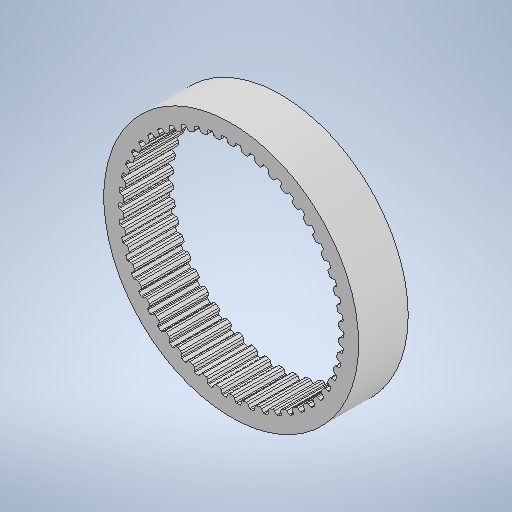
# Autodesk Inventor part: 3D_belt-MXL-50
Saved by Autodesk Inventor 2025.3 (Build 293356030, 356C)
## iProperties
Created: 2026-02-24
Part Number: 3D_belt-MXL-50
Material: 一般
Document SubType Name: Modeling
Designer: ibuki_ono
Density: 1 g/cm^3
Appearance: 既定
Author: ibuki_ono
## iProperties of the stored document 3D_belt-MXL-50_3D プリント.ipt
Created: 2026-02-24
Part Number: 3D_belt-MXL-50_3D プリント
Material: 一般
Document SubType Name: Modeling
Designer: ibuki_ono
Density: 1 g/cm^3
Appearance: 既定
Author: ibuki_ono
Autodesk Inventor part; units mm, degrees
ref_plane "YZ Plane" through (0, 0, 0) normal (1, 0, 0) x (0, 1, 0)
ref_plane "XZ Plane" through (0, 0, 0) normal (0, 1, 0) x (-1, 0, 0)
ref_plane "XY Plane" through (0, 0, 0) normal (0, 0, 1) x (1, 0, 0)
sketch "スケッチ1" plane through (0, 0, 0) normal (0, 0, 1) x (1, 0, 0)
  arc A0 (2.7438, 15.6779) -> (2.6089, 15.6108) centre (2.7219, 15.5528) ccw
  line L0 (2.6089, 15.6108) -> (2.406, 15.2159)
  arc A1 (2.1482, 15.08) -> (2.406, 15.2159) centre (2.18, 15.332) ccw
  line L1 (2.1482, 15.08) -> (1.6695, 15.1405)
  arc A2 (1.4537, 15.3362) -> (1.6695, 15.1405) centre (1.7014, 15.3925) ccw
  line L2 (1.4537, 15.3362) -> (1.3553, 15.7692)
  arc A3 (1.3553, 15.7692) -> (1.2414, 15.8677) centre (1.2315, 15.741) ccw
  arc A4 (1.2414, 15.8677) -> (0.7572, 15.8981) centre (0, 0) ccw
  arc A5 (0.7572, 15.8981) -> (0.6318, 15.8147) centre (0.7511, 15.7713) ccw
  line L3 (0.6318, 15.8147) -> (0.4799, 15.3975)
  arc A6 (0.2412, 15.2303) -> (0.4799, 15.3975) centre (0.2412, 15.4843) ccw
  line L4 (0.2412, 15.2303) -> (-0.2412, 15.2303)
  arc A7 (-0.4799, 15.3975) -> (-0.2412, 15.2303) centre (-0.2412, 15.4843) ccw
  line L5 (-0.4799, 15.3975) -> (-0.6318, 15.8147)
  arc A8 (-0.6318, 15.8147) -> (-0.7572, 15.8981) centre (-0.7511, 15.7713) ccw
  arc A9 (-0.7572, 15.8981) -> (-1.2414, 15.8677) centre (0, 0) ccw
  arc A10 (-1.2414, 15.8677) -> (-1.3553, 15.7692) centre (-1.2315, 15.741) ccw
  line L6 (-1.3553, 15.7692) -> (-1.4537, 15.3362)
  arc A11 (-1.6695, 15.1405) -> (-1.4537, 15.3362) centre (-1.7014, 15.3925) ccw
  line L7 (-1.6695, 15.1405) -> (-2.1482, 15.08)
  arc A12 (-2.406, 15.2159) -> (-2.1482, 15.08) centre (-2.18, 15.332) ccw
  line L8 (-2.406, 15.2159) -> (-2.6089, 15.6108)
  arc A13 (-2.6089, 15.6108) -> (-2.7438, 15.6779) centre (-2.7219, 15.5528) ccw
  arc A14 (-2.7438, 15.6779) -> (-3.2203, 15.587) centre (0, 0) ccw
  arc A15 (-3.2203, 15.587) -> (-3.321, 15.475) centre (-3.1946, 15.4626) ccw
  line L9 (-3.321, 15.475) -> (-3.3643, 15.0331)
  arc A16 (-3.554, 14.8118) -> (-3.3643, 15.0331) centre (-3.6171, 15.0579) ccw
  line L10 (-3.554, 14.8118) -> (-4.0213, 14.6919)
  arc A17 (-4.294, 14.7944) -> (-4.0213, 14.6919) centre (-4.0845, 14.9379) ccw
  line L11 (-4.294, 14.7944) -> (-4.5449, 15.1607)
  arc A18 (-4.5449, 15.1607) -> (-4.6871, 15.2104) centre (-4.6497, 15.089) ccw
  arc A19 (-4.6871, 15.2104) -> (-5.1485, 15.0604) centre (0, 0) ccw
  arc A20 (-5.1485, 15.0604) -> (-5.2344, 14.9367) centre (-5.1074, 14.9403) ccw
  line L12 (-5.2344, 14.9367) -> (-5.222, 14.4929)
  arc A21 (-5.3824, 14.2496) -> (-5.222, 14.4929) centre (-5.4759, 14.4858) ccw
  line L13 (-5.3824, 14.2496) -> (-5.831, 14.072)
  arc A22 (-6.1144, 14.1395) -> (-5.831, 14.072) centre (-5.9245, 14.3082) ccw
  line L14 (-6.1144, 14.1395) -> (-6.4092, 14.4716)
  arc A23 (-6.4092, 14.4716) -> (-6.5565, 14.503) centre (-6.5042, 14.3872) ccw
  arc A24 (-6.5565, 14.503) -> (-6.9955, 14.2964) centre (0, 0) ccw
  arc A25 (-6.9955, 14.2964) -> (-7.0651, 14.1629) centre (-6.9396, 14.1823) ccw
  line L15 (-7.0651, 14.1629) -> (-6.9972, 13.7241)
  arc A26 (-7.1259, 13.4627) -> (-6.9972, 13.7241) centre (-7.2482, 13.6853) ccw
  line L16 (-7.1259, 13.4627) -> (-7.5487, 13.2302)
  arc A27 (-7.8384, 13.2617) -> (-7.5487, 13.2302) centre (-7.671, 13.4528) ccw
  line L17 (-7.8384, 13.2617) -> (-8.1724, 13.5542)
  arc A28 (-8.1724, 13.5542) -> (-8.3225, 13.5669) centre (-8.2561, 13.4586) ccw
  arc A29 (-8.3225, 13.5669) -> (-8.7321, 13.3069) centre (0, 0) ccw
  arc A30 (-8.7321, 13.3069) -> (-8.7845, 13.1657) centre (-8.6624, 13.2007) ccw
  line L18 (-8.7845, 13.1657) -> (-8.6621, 12.7389)
  arc A31 (-8.757, 12.4634) -> (-8.6621, 12.7389) centre (-8.9063, 12.6689) ccw
  line L19 (-8.757, 12.4634) -> (-9.1473, 12.1798)
  arc A32 (-9.4387, 12.1747) -> (-9.1473, 12.1798) centre (-9.2966, 12.3853) ccw
  line L20 (-9.4387, 12.1747) -> (-9.8068, 12.423)
  arc A33 (-9.8068, 12.423) -> (-9.9572, 12.4168) centre (-9.8778, 12.3177) ccw
  arc A34 (-9.9572, 12.4168) -> (-10.3311, 12.1076) centre (0, 0) ccw
  arc A35 (-10.3311, 12.1076) -> (-10.3654, 11.9609) centre (-10.2486, 12.0109) ccw
  line L21 (-10.3654, 11.9609) -> (-10.1904, 11.5528)
  arc A36 (-10.25, 11.2676) -> (-10.1904, 11.5528) centre (-10.4239, 11.4527) ccw
  line L22 (-10.25, 11.2676) -> (-10.6017, 10.9373)
  arc A37 (-10.8901, 10.8957) -> (-10.6017, 10.9373) centre (-10.7756, 11.1225) ccw
  line L23 (-10.8901, 10.8957) -> (-11.2865, 11.0959)
  arc A38 (-11.2865, 11.0959) -> (-11.435, 11.0709) centre (-11.3437, 10.9826) ccw
  arc A39 (-11.435, 11.0709) -> (-11.7671, 10.7173) centre (0, 0) ccw
  arc A40 (-11.7671, 10.7173) -> (-11.7827, 10.5675) centre (-11.6732, 10.6317) ccw
  line L24 (-11.7827, 10.5675) -> (-11.558, 10.1845)
  arc A41 (-11.5814, 9.8941) -> (-11.558, 10.1845) centre (-11.7771, 10.056) ccw
  line L25 (-11.5814, 9.8941) -> (-11.889, 9.5223)
  arc A42 (-12.1699, 9.4449) -> (-11.889, 9.5223) centre (-12.0847, 9.6842) ccw
  line L26 (-12.1699, 9.4449) -> (-12.5882, 9.5939)
  arc A43 (-12.5882, 9.5939) -> (-12.7324, 9.5504) centre (-12.6308, 9.4742) ccw
  arc A44 (-12.7324, 9.5504) -> (-13.0175, 9.1579) centre (0, 0) ccw
  arc A45 (-13.0175, 9.1579) -> (-13.0143, 9.0074) centre (-12.9136, 9.0849) ccw
  line L27 (-13.0143, 9.0074) -> (-12.7434, 8.6556)
  arc A46 (-12.7301, 8.3645) -> (-12.7434, 8.6556) centre (-12.9446, 8.5006) ccw
  line L28 (-12.7301, 8.3645) -> (-12.9887, 7.9571)
  arc A47 (-13.2577, 7.8452) -> (-12.9887, 7.9571) centre (-13.2031, 8.0932) ccw
  line L29 (-13.2577, 7.8452) -> (-13.6913, 7.9405)
  arc A48 (-13.6913, 7.9405) -> (-13.8289, 7.8793) centre (-13.7186, 7.8165) ccw
  arc A49 (-13.8289, 7.8793) -> (-14.0627, 7.4542) centre (0, 0) ccw
  arc A50 (-14.0627, 7.4542) -> (-14.0406, 7.3052) centre (-13.9505, 7.3947) ccw
  line L30 (-14.0406, 7.3052) -> (-13.7277, 6.9902)
  arc A51 (-13.6781, 6.7031) -> (-13.7277, 6.9902) centre (-13.9079, 6.8112) ccw
  line L31 (-13.6781, 6.7031) -> (-13.8835, 6.2665)
  arc A52 (-14.1364, 6.1217) -> (-13.8835, 6.2665) centre (-14.1134, 6.3746) ccw
  line L32 (-14.1364, 6.1217) -> (-14.5786, 6.1619)
  arc A53 (-14.5786, 6.1619) -> (-14.7074, 6.084) centre (-14.5901, 6.0354) ccw
  arc A54 (-14.7074, 6.084) -> (-14.886, 5.6329) centre (0, 0) ccw
  arc A55 (-14.886, 5.6329) -> (-14.8454, 5.4879) centre (-14.7673, 5.588) ccw
  line L33 (-14.8454, 5.4879) -> (-14.4956, 5.2145)
  arc A56 (-14.4104, 4.9359) -> (-14.4956, 5.2145) centre (-14.6519, 5.0144) ccw
  line L34 (-14.4104, 4.9359) -> (-14.5595, 4.477)
  arc A57 (-14.7922, 4.3016) -> (-14.5595, 4.477) centre (-14.801, 4.5555) ccw
  line L35 (-14.7922, 4.3016) -> (-15.2359, 4.2861)
  arc A58 (-15.2359, 4.2861) -> (-15.354, 4.1927) centre (-15.2315, 4.1592) ccw
  arc A59 (-15.354, 4.1927) -> (-15.4746, 3.7228) centre (0, 0) ccw
  arc A60 (-15.4746, 3.7228) -> (-15.4162, 3.584) centre (-15.3512, 3.6931) ccw
  line L36 (-15.4162, 3.584) -> (-15.0348, 3.3566)
  arc A61 (-14.9154, 3.0909) -> (-15.0348, 3.3566) centre (-15.1649, 3.1385) ccw
  line L37 (-14.9154, 3.0909) -> (-15.0058, 2.6169)
  arc A62 (-15.2147, 2.4138) -> (-15.0058, 2.6169) centre (-15.2553, 2.6645) ccw
  line L38 (-15.2147, 2.4138) -> (-15.653, 2.3428)
  arc A63 (-15.653, 2.3428) -> (-15.7584, 2.2353) centre (-15.6327, 2.2174) ccw
  arc A64 (-15.7584, 2.2353) -> (-15.8192, 1.7539) centre (0, 0) ccw
  arc A65 (-15.8192, 1.7539) -> (-15.7438, 1.6236) centre (-15.693, 1.7399) ccw
  line L39 (-15.7438, 1.6236) -> (-15.337, 1.4458)
  arc A66 (-15.1851, 1.1971) -> (-15.337, 1.4458) centre (-15.4386, 1.213) ccw
  line L40 (-15.1851, 1.1971) -> (-15.2154, 0.7155)
  arc A67 (-15.3972, 0.4878) -> (-15.2154, 0.7155) centre (-15.4689, 0.7315) ccw
  line L41 (-15.3972, 0.4878) -> (-15.8232, 0.3625)
  arc A68 (-15.8232, 0.3625) -> (-15.9143, 0.2426) centre (-15.7873, 0.2406) ccw
  arc A69 (-15.9143, 0.2426) -> (-15.9143, -0.2426) centre (0, 0) ccw
  arc A70 (-15.9143, -0.2426) -> (-15.8232, -0.3625) centre (-15.7873, -0.2406) ccw
  line L42 (-15.8232, -0.3625) -> (-15.3972, -0.4878)
  arc A71 (-15.2154, -0.7155) -> (-15.3972, -0.4878) centre (-15.4689, -0.7315) ccw
  line L43 (-15.2154, -0.7155) -> (-15.1851, -1.1971)
  arc A72 (-15.337, -1.4458) -> (-15.1851, -1.1971) centre (-15.4386, -1.213) ccw
  line L44 (-15.337, -1.4458) -> (-15.7438, -1.6236)
  arc A73 (-15.7438, -1.6236) -> (-15.8192, -1.7539) centre (-15.693, -1.7399) ccw
  arc A74 (-15.8192, -1.7539) -> (-15.7584, -2.2353) centre (0, 0) ccw
  arc A75 (-15.7584, -2.2353) -> (-15.653, -2.3428) centre (-15.6327, -2.2174) ccw
  line L45 (-15.653, -2.3428) -> (-15.2147, -2.4138)
  arc A76 (-15.0058, -2.6169) -> (-15.2147, -2.4138) centre (-15.2553, -2.6645) ccw
  line L46 (-15.0058, -2.6169) -> (-14.9154, -3.0909)
  arc A77 (-15.0348, -3.3566) -> (-14.9154, -3.0909) centre (-15.1649, -3.1385) ccw
  line L47 (-15.0348, -3.3566) -> (-15.4162, -3.584)
  arc A78 (-15.4162, -3.584) -> (-15.4746, -3.7228) centre (-15.3512, -3.6931) ccw
  arc A79 (-15.4746, -3.7228) -> (-15.354, -4.1927) centre (0, 0) ccw
  arc A80 (-15.354, -4.1927) -> (-15.2359, -4.2861) centre (-15.2315, -4.1592) ccw
  line L48 (-15.2359, -4.2861) -> (-14.7922, -4.3016)
  arc A81 (-14.5595, -4.477) -> (-14.7922, -4.3016) centre (-14.801, -4.5555) ccw
  line L49 (-14.5595, -4.477) -> (-14.4104, -4.9359)
  arc A82 (-14.4956, -5.2145) -> (-14.4104, -4.9359) centre (-14.6519, -5.0144) ccw
  line L50 (-14.4956, -5.2145) -> (-14.8454, -5.4879)
  arc A83 (-14.8454, -5.4879) -> (-14.886, -5.6329) centre (-14.7673, -5.588) ccw
  arc A84 (-14.886, -5.6329) -> (-14.7074, -6.084) centre (0, 0) ccw
  arc A85 (-14.7074, -6.084) -> (-14.5786, -6.1619) centre (-14.5901, -6.0354) ccw
  line L51 (-14.5786, -6.1619) -> (-14.1364, -6.1217)
  arc A86 (-13.8835, -6.2665) -> (-14.1364, -6.1217) centre (-14.1134, -6.3746) ccw
  line L52 (-13.8835, -6.2665) -> (-13.6781, -6.7031)
  arc A87 (-13.7277, -6.9902) -> (-13.6781, -6.7031) centre (-13.9079, -6.8112) ccw
  line L53 (-13.7277, -6.9902) -> (-14.0406, -7.3052)
  arc A88 (-14.0406, -7.3052) -> (-14.0627, -7.4542) centre (-13.9505, -7.3947) ccw
  arc A89 (-14.0627, -7.4542) -> (-13.8289, -7.8793) centre (0, 0) ccw
  arc A90 (-13.8289, -7.8793) -> (-13.6913, -7.9405) centre (-13.7186, -7.8165) ccw
  line L54 (-13.6913, -7.9405) -> (-13.2577, -7.8452)
  arc A91 (-12.9887, -7.9571) -> (-13.2577, -7.8452) centre (-13.2031, -8.0932) ccw
  line L55 (-12.9887, -7.9571) -> (-12.7301, -8.3645)
  arc A92 (-12.7434, -8.6556) -> (-12.7301, -8.3645) centre (-12.9446, -8.5006) ccw
  line L56 (-12.7434, -8.6556) -> (-13.0143, -9.0074)
  arc A93 (-13.0143, -9.0074) -> (-13.0175, -9.1579) centre (-12.9136, -9.0849) ccw
  arc A94 (-13.0175, -9.1579) -> (-12.7324, -9.5504) centre (0, 0) ccw
  arc A95 (-12.7324, -9.5504) -> (-12.5882, -9.5939) centre (-12.6308, -9.4742) ccw
  line L57 (-12.5882, -9.5939) -> (-12.1699, -9.4449)
  arc A96 (-11.889, -9.5223) -> (-12.1699, -9.4449) centre (-12.0847, -9.6842) ccw
  line L58 (-11.889, -9.5223) -> (-11.5814, -9.8941)
  arc A97 (-11.558, -10.1845) -> (-11.5814, -9.8941) centre (-11.7771, -10.056) ccw
  line L59 (-11.558, -10.1845) -> (-11.7827, -10.5675)
  arc A98 (-11.7827, -10.5675) -> (-11.7671, -10.7173) centre (-11.6732, -10.6317) ccw
  arc A99 (-11.7671, -10.7173) -> (-11.435, -11.0709) centre (0, 0) ccw
  arc A100 (-11.435, -11.0709) -> (-11.2865, -11.0959) centre (-11.3437, -10.9826) ccw
  line L60 (-11.2865, -11.0959) -> (-10.8901, -10.8957)
  arc A101 (-10.6017, -10.9373) -> (-10.8901, -10.8957) centre (-10.7756, -11.1225) ccw
  line L61 (-10.6017, -10.9373) -> (-10.25, -11.2676)
  arc A102 (-10.1904, -11.5528) -> (-10.25, -11.2676) centre (-10.4239, -11.4527) ccw
  line L62 (-10.1904, -11.5528) -> (-10.3654, -11.9609)
  arc A103 (-10.3654, -11.9609) -> (-10.3311, -12.1076) centre (-10.2486, -12.0109) ccw
  arc A104 (-10.3311, -12.1076) -> (-9.9572, -12.4168) centre (0, 0) ccw
  arc A105 (-9.9572, -12.4168) -> (-9.8068, -12.423) centre (-9.8778, -12.3177) ccw
  line L63 (-9.8068, -12.423) -> (-9.4387, -12.1747)
  arc A106 (-9.1473, -12.1798) -> (-9.4387, -12.1747) centre (-9.2966, -12.3853) ccw
  line L64 (-9.1473, -12.1798) -> (-8.757, -12.4634)
  arc A107 (-8.6621, -12.7389) -> (-8.757, -12.4634) centre (-8.9063, -12.6689) ccw
  line L65 (-8.6621, -12.7389) -> (-8.7845, -13.1657)
  arc A108 (-8.7845, -13.1657) -> (-8.7321, -13.3069) centre (-8.6624, -13.2007) ccw
  arc A109 (-8.7321, -13.3069) -> (-8.3225, -13.5669) centre (0, 0) ccw
  arc A110 (-8.3225, -13.5669) -> (-8.1724, -13.5542) centre (-8.2561, -13.4586) ccw
  line L66 (-8.1724, -13.5542) -> (-7.8384, -13.2617)
  arc A111 (-7.5487, -13.2302) -> (-7.8384, -13.2617) centre (-7.671, -13.4528) ccw
  line L67 (-7.5487, -13.2302) -> (-7.1259, -13.4627)
  arc A112 (-6.9972, -13.7241) -> (-7.1259, -13.4627) centre (-7.2482, -13.6853) ccw
  line L68 (-6.9972, -13.7241) -> (-7.0651, -14.1629)
  arc A113 (-7.0651, -14.1629) -> (-6.9955, -14.2964) centre (-6.9396, -14.1823) ccw
  arc A114 (-6.9955, -14.2964) -> (-6.5565, -14.503) centre (0, 0) ccw
  arc A115 (-6.5565, -14.503) -> (-6.4092, -14.4716) centre (-6.5042, -14.3872) ccw
  line L69 (-6.4092, -14.4716) -> (-6.1144, -14.1395)
  arc A116 (-5.831, -14.072) -> (-6.1144, -14.1395) centre (-5.9245, -14.3082) ccw
  line L70 (-5.831, -14.072) -> (-5.3824, -14.2496)
  arc A117 (-5.222, -14.4929) -> (-5.3824, -14.2496) centre (-5.4759, -14.4858) ccw
  line L71 (-5.222, -14.4929) -> (-5.2344, -14.9367)
  arc A118 (-5.2344, -14.9367) -> (-5.1485, -15.0604) centre (-5.1074, -14.9403) ccw
  arc A119 (-5.1485, -15.0604) -> (-4.6871, -15.2104) centre (0, 0) ccw
  arc A120 (-4.6871, -15.2104) -> (-4.5449, -15.1607) centre (-4.6497, -15.089) ccw
  line L72 (-4.5449, -15.1607) -> (-4.294, -14.7944)
  arc A121 (-4.0213, -14.6919) -> (-4.294, -14.7944) centre (-4.0845, -14.9379) ccw
  line L73 (-4.0213, -14.6919) -> (-3.554, -14.8118)
  arc A122 (-3.3643, -15.0331) -> (-3.554, -14.8118) centre (-3.6171, -15.0579) ccw
  line L74 (-3.3643, -15.0331) -> (-3.321, -15.475)
  arc A123 (-3.321, -15.475) -> (-3.2203, -15.587) centre (-3.1946, -15.4626) ccw
  arc A124 (-3.2203, -15.587) -> (-2.7438, -15.6779) centre (0, 0) ccw
  arc A125 (-2.7438, -15.6779) -> (-2.6089, -15.6108) centre (-2.7219, -15.5528) ccw
  line L75 (-2.6089, -15.6108) -> (-2.406, -15.2159)
  arc A126 (-2.1482, -15.08) -> (-2.406, -15.2159) centre (-2.18, -15.332) ccw
  line L76 (-2.1482, -15.08) -> (-1.6695, -15.1405)
  arc A127 (-1.4537, -15.3362) -> (-1.6695, -15.1405) centre (-1.7014, -15.3925) ccw
  line L77 (-1.4537, -15.3362) -> (-1.3553, -15.7692)
  arc A128 (-1.3553, -15.7692) -> (-1.2414, -15.8677) centre (-1.2315, -15.741) ccw
  arc A129 (-1.2414, -15.8677) -> (-0.7572, -15.8981) centre (0, 0) ccw
  arc A130 (-0.7572, -15.8981) -> (-0.6318, -15.8147) centre (-0.7511, -15.7713) ccw
  line L78 (-0.6318, -15.8147) -> (-0.4799, -15.3975)
  arc A131 (-0.2412, -15.2303) -> (-0.4799, -15.3975) centre (-0.2412, -15.4843) ccw
  line L79 (-0.2412, -15.2303) -> (0.2412, -15.2303)
  arc A132 (0.4799, -15.3975) -> (0.2412, -15.2303) centre (0.2412, -15.4843) ccw
  line L80 (0.4799, -15.3975) -> (0.6318, -15.8147)
  arc A133 (0.6318, -15.8147) -> (0.7572, -15.8981) centre (0.7511, -15.7713) ccw
  arc A134 (0.7572, -15.8981) -> (1.2414, -15.8677) centre (0, 0) ccw
  arc A135 (1.2414, -15.8677) -> (1.3553, -15.7692) centre (1.2315, -15.741) ccw
  line L81 (1.3553, -15.7692) -> (1.4537, -15.3362)
  arc A136 (1.6695, -15.1405) -> (1.4537, -15.3362) centre (1.7014, -15.3925) ccw
  line L82 (1.6695, -15.1405) -> (2.1482, -15.08)
  arc A137 (2.406, -15.2159) -> (2.1482, -15.08) centre (2.18, -15.332) ccw
  line L83 (2.406, -15.2159) -> (2.6089, -15.6108)
  arc A138 (2.6089, -15.6108) -> (2.7438, -15.6779) centre (2.7219, -15.5528) ccw
  arc A139 (2.7438, -15.6779) -> (3.2203, -15.587) centre (0, 0) ccw
  arc A140 (3.2203, -15.587) -> (3.321, -15.475) centre (3.1946, -15.4626) ccw
  line L84 (3.321, -15.475) -> (3.3643, -15.0331)
  arc A141 (3.554, -14.8118) -> (3.3643, -15.0331) centre (3.6171, -15.0579) ccw
  line L85 (3.554, -14.8118) -> (4.0213, -14.6919)
  arc A142 (4.294, -14.7944) -> (4.0213, -14.6919) centre (4.0845, -14.9379) ccw
  line L86 (4.294, -14.7944) -> (4.5449, -15.1607)
  arc A143 (4.5449, -15.1607) -> (4.6871, -15.2104) centre (4.6497, -15.089) ccw
  arc A144 (4.6871, -15.2104) -> (5.1485, -15.0604) centre (0, 0) ccw
  arc A145 (5.1485, -15.0604) -> (5.2344, -14.9367) centre (5.1074, -14.9403) ccw
  line L87 (5.2344, -14.9367) -> (5.222, -14.4929)
  arc A146 (5.3824, -14.2496) -> (5.222, -14.4929) centre (5.4759, -14.4858) ccw
  line L88 (5.3824, -14.2496) -> (5.831, -14.072)
  arc A147 (6.1144, -14.1395) -> (5.831, -14.072) centre (5.9245, -14.3082) ccw
  line L89 (6.1144, -14.1395) -> (6.4092, -14.4716)
  arc A148 (6.4092, -14.4716) -> (6.5565, -14.503) centre (6.5042, -14.3872) ccw
  arc A149 (6.5565, -14.503) -> (6.9955, -14.2964) centre (0, 0) ccw
  arc A150 (6.9955, -14.2964) -> (7.0651, -14.1629) centre (6.9396, -14.1823) ccw
  line L90 (7.0651, -14.1629) -> (6.9972, -13.7241)
  arc A151 (7.1259, -13.4627) -> (6.9972, -13.7241) centre (7.2482, -13.6853) ccw
  line L91 (7.1259, -13.4627) -> (7.5487, -13.2302)
  arc A152 (7.8384, -13.2617) -> (7.5487, -13.2302) centre (7.671, -13.4528) ccw
  line L92 (7.8384, -13.2617) -> (8.1724, -13.5542)
  arc A153 (8.1724, -13.5542) -> (8.3225, -13.5669) centre (8.2561, -13.4586) ccw
  arc A154 (8.3225, -13.5669) -> (8.7321, -13.3069) centre (0, 0) ccw
  arc A155 (8.7321, -13.3069) -> (8.7845, -13.1657) centre (8.6624, -13.2007) ccw
  line L93 (8.7845, -13.1657) -> (8.6621, -12.7389)
  arc A156 (8.757, -12.4634) -> (8.6621, -12.7389) centre (8.9063, -12.6689) ccw
  line L94 (8.757, -12.4634) -> (9.1473, -12.1798)
  arc A157 (9.4387, -12.1747) -> (9.1473, -12.1798) centre (9.2966, -12.3853) ccw
  line L95 (9.4387, -12.1747) -> (9.8068, -12.423)
  arc A158 (9.8068, -12.423) -> (9.9572, -12.4168) centre (9.8778, -12.3177) ccw
  arc A159 (9.9572, -12.4168) -> (10.3311, -12.1076) centre (0, 0) ccw
  arc A160 (10.3311, -12.1076) -> (10.3654, -11.9609) centre (10.2486, -12.0109) ccw
  line L96 (10.3654, -11.9609) -> (10.1904, -11.5528)
  arc A161 (10.25, -11.2676) -> (10.1904, -11.5528) centre (10.4239, -11.4527) ccw
  line L97 (10.25, -11.2676) -> (10.6017, -10.9373)
  arc A162 (10.8901, -10.8957) -> (10.6017, -10.9373) centre (10.7756, -11.1225) ccw
  line L98 (10.8901, -10.8957) -> (11.2865, -11.0959)
  arc A163 (11.2865, -11.0959) -> (11.435, -11.0709) centre (11.3437, -10.9826) ccw
  arc A164 (11.435, -11.0709) -> (11.7671, -10.7173) centre (0, 0) ccw
  arc A165 (11.7671, -10.7173) -> (11.7827, -10.5675) centre (11.6732, -10.6317) ccw
  line L99 (11.7827, -10.5675) -> (11.558, -10.1845)
  arc A166 (11.5814, -9.8941) -> (11.558, -10.1845) centre (11.7771, -10.056) ccw
  line L100 (11.5814, -9.8941) -> (11.889, -9.5223)
  arc A167 (12.1699, -9.4449) -> (11.889, -9.5223) centre (12.0847, -9.6842) ccw
  line L101 (12.1699, -9.4449) -> (12.5882, -9.5939)
  arc A168 (12.5882, -9.5939) -> (12.7324, -9.5504) centre (12.6308, -9.4742) ccw
  arc A169 (12.7324, -9.5504) -> (13.0175, -9.1579) centre (0, 0) ccw
  arc A170 (13.0175, -9.1579) -> (13.0143, -9.0074) centre (12.9136, -9.0849) ccw
  line L102 (13.0143, -9.0074) -> (12.7434, -8.6556)
  arc A171 (12.7301, -8.3645) -> (12.7434, -8.6556) centre (12.9446, -8.5006) ccw
  line L103 (12.7301, -8.3645) -> (12.9887, -7.9571)
  arc A172 (13.2577, -7.8452) -> (12.9887, -7.9571) centre (13.2031, -8.0932) ccw
  line L104 (13.2577, -7.8452) -> (13.6913, -7.9405)
  arc A173 (13.6913, -7.9405) -> (13.8289, -7.8793) centre (13.7186, -7.8165) ccw
  arc A174 (13.8289, -7.8793) -> (14.0627, -7.4542) centre (0, 0) ccw
  arc A175 (14.0627, -7.4542) -> (14.0406, -7.3052) centre (13.9505, -7.3947) ccw
  line L105 (14.0406, -7.3052) -> (13.7277, -6.9902)
  arc A176 (13.6781, -6.7031) -> (13.7277, -6.9902) centre (13.9079, -6.8112) ccw
  line L106 (13.6781, -6.7031) -> (13.8835, -6.2665)
  arc A177 (14.1364, -6.1217) -> (13.8835, -6.2665) centre (14.1134, -6.3746) ccw
  line L107 (14.1364, -6.1217) -> (14.5786, -6.1619)
  arc A178 (14.5786, -6.1619) -> (14.7074, -6.084) centre (14.5901, -6.0354) ccw
  arc A179 (14.7074, -6.084) -> (14.886, -5.6329) centre (0, 0) ccw
  arc A180 (14.886, -5.6329) -> (14.8454, -5.4879) centre (14.7673, -5.588) ccw
  line L108 (14.8454, -5.4879) -> (14.4956, -5.2145)
  arc A181 (14.4104, -4.9359) -> (14.4956, -5.2145) centre (14.6519, -5.0144) ccw
  line L109 (14.4104, -4.9359) -> (14.5595, -4.477)
  arc A182 (14.7922, -4.3016) -> (14.5595, -4.477) centre (14.801, -4.5555) ccw
  line L110 (14.7922, -4.3016) -> (15.2359, -4.2861)
  arc A183 (15.2359, -4.2861) -> (15.354, -4.1927) centre (15.2315, -4.1592) ccw
  arc A184 (15.354, -4.1927) -> (15.4746, -3.7228) centre (0, 0) ccw
  arc A185 (15.4746, -3.7228) -> (15.4162, -3.584) centre (15.3512, -3.6931) ccw
  line L111 (15.4162, -3.584) -> (15.0348, -3.3566)
  arc A186 (14.9154, -3.0909) -> (15.0348, -3.3566) centre (15.1649, -3.1385) ccw
  line L112 (14.9154, -3.0909) -> (15.0058, -2.6169)
  arc A187 (15.2147, -2.4138) -> (15.0058, -2.6169) centre (15.2553, -2.6645) ccw
  line L113 (15.2147, -2.4138) -> (15.653, -2.3428)
  arc A188 (15.653, -2.3428) -> (15.7584, -2.2353) centre (15.6327, -2.2174) ccw
  arc A189 (15.7584, -2.2353) -> (15.8192, -1.7539) centre (0, 0) ccw
  arc A190 (15.8192, -1.7539) -> (15.7438, -1.6236) centre (15.693, -1.7399) ccw
  line L114 (15.7438, -1.6236) -> (15.337, -1.4458)
  arc A191 (15.1851, -1.1971) -> (15.337, -1.4458) centre (15.4386, -1.213) ccw
  line L115 (15.1851, -1.1971) -> (15.2154, -0.7155)
  arc A192 (15.3972, -0.4878) -> (15.2154, -0.7155) centre (15.4689, -0.7315) ccw
  line L116 (15.3972, -0.4878) -> (15.8232, -0.3625)
  arc A193 (15.8232, -0.3625) -> (15.9143, -0.2426) centre (15.7873, -0.2406) ccw
  arc A194 (15.9143, -0.2426) -> (15.9143, 0.2426) centre (0, 0) ccw
  arc A195 (15.9143, 0.2426) -> (15.8232, 0.3625) centre (15.7873, 0.2406) ccw
  line L117 (15.8232, 0.3625) -> (15.3972, 0.4878)
  arc A196 (15.2154, 0.7155) -> (15.3972, 0.4878) centre (15.4689, 0.7315) ccw
  line L118 (15.2154, 0.7155) -> (15.1851, 1.1971)
  arc A197 (15.337, 1.4458) -> (15.1851, 1.1971) centre (15.4386, 1.213) ccw
  line L119 (15.337, 1.4458) -> (15.7438, 1.6236)
  arc A198 (15.7438, 1.6236) -> (15.8192, 1.7539) centre (15.693, 1.7399) ccw
  arc A199 (15.8192, 1.7539) -> (15.7584, 2.2353) centre (0, 0) ccw
  arc A200 (15.7584, 2.2353) -> (15.653, 2.3428) centre (15.6327, 2.2174) ccw
  line L120 (15.653, 2.3428) -> (15.2147, 2.4138)
  arc A201 (15.0058, 2.6169) -> (15.2147, 2.4138) centre (15.2553, 2.6645) ccw
  line L121 (15.0058, 2.6169) -> (14.9154, 3.0909)
  arc A202 (15.0348, 3.3566) -> (14.9154, 3.0909) centre (15.1649, 3.1385) ccw
  line L122 (15.0348, 3.3566) -> (15.4162, 3.584)
  arc A203 (15.4162, 3.584) -> (15.4746, 3.7228) centre (15.3512, 3.6931) ccw
  arc A204 (15.4746, 3.7228) -> (15.354, 4.1927) centre (0, 0) ccw
  arc A205 (15.354, 4.1927) -> (15.2359, 4.2861) centre (15.2315, 4.1592) ccw
  line L123 (15.2359, 4.2861) -> (14.7922, 4.3016)
  arc A206 (14.5595, 4.477) -> (14.7922, 4.3016) centre (14.801, 4.5555) ccw
  line L124 (14.5595, 4.477) -> (14.4104, 4.9359)
  arc A207 (14.4956, 5.2145) -> (14.4104, 4.9359) centre (14.6519, 5.0144) ccw
  line L125 (14.4956, 5.2145) -> (14.8454, 5.4879)
  arc A208 (14.8454, 5.4879) -> (14.886, 5.6329) centre (14.7673, 5.588) ccw
  arc A209 (14.886, 5.6329) -> (14.7074, 6.084) centre (0, 0) ccw
  arc A210 (14.7074, 6.084) -> (14.5786, 6.1619) centre (14.5901, 6.0354) ccw
  line L126 (14.5786, 6.1619) -> (14.1364, 6.1217)
  arc A211 (13.8835, 6.2665) -> (14.1364, 6.1217) centre (14.1134, 6.3746) ccw
  line L127 (13.8835, 6.2665) -> (13.6781, 6.7031)
  arc A212 (13.7277, 6.9902) -> (13.6781, 6.7031) centre (13.9079, 6.8112) ccw
  line L128 (13.7277, 6.9902) -> (14.0406, 7.3052)
  arc A213 (14.0406, 7.3052) -> (14.0627, 7.4542) centre (13.9505, 7.3947) ccw
  arc A214 (14.0627, 7.4542) -> (13.8289, 7.8793) centre (0, 0) ccw
  arc A215 (13.8289, 7.8793) -> (13.6913, 7.9405) centre (13.7186, 7.8165) ccw
  line L129 (13.6913, 7.9405) -> (13.2577, 7.8452)
  arc A216 (12.9887, 7.9571) -> (13.2577, 7.8452) centre (13.2031, 8.0932) ccw
  line L130 (12.9887, 7.9571) -> (12.7301, 8.3645)
  arc A217 (12.7434, 8.6556) -> (12.7301, 8.3645) centre (12.9446, 8.5006) ccw
  line L131 (12.7434, 8.6556) -> (13.0143, 9.0074)
  arc A218 (13.0143, 9.0074) -> (13.0175, 9.1579) centre (12.9136, 9.0849) ccw
  arc A219 (13.0175, 9.1579) -> (12.7324, 9.5504) centre (0, 0) ccw
  arc A220 (12.7324, 9.5504) -> (12.5882, 9.5939) centre (12.6308, 9.4742) ccw
  line L132 (12.5882, 9.5939) -> (12.1699, 9.4449)
  arc A221 (11.889, 9.5223) -> (12.1699, 9.4449) centre (12.0847, 9.6842) ccw
  line L133 (11.889, 9.5223) -> (11.5814, 9.8941)
  arc A222 (11.558, 10.1845) -> (11.5814, 9.8941) centre (11.7771, 10.056) ccw
  line L134 (11.558, 10.1845) -> (11.7827, 10.5675)
  arc A223 (11.7827, 10.5675) -> (11.7671, 10.7173) centre (11.6732, 10.6317) ccw
  arc A224 (11.7671, 10.7173) -> (11.435, 11.0709) centre (0, 0) ccw
  arc A225 (11.435, 11.0709) -> (11.2865, 11.0959) centre (11.3437, 10.9826) ccw
  line L135 (11.2865, 11.0959) -> (10.8901, 10.8957)
  arc A226 (10.6017, 10.9373) -> (10.8901, 10.8957) centre (10.7756, 11.1225) ccw
  line L136 (10.6017, 10.9373) -> (10.25, 11.2676)
  arc A227 (10.1904, 11.5528) -> (10.25, 11.2676) centre (10.4239, 11.4527) ccw
  line L137 (10.1904, 11.5528) -> (10.3654, 11.9609)
  arc A228 (10.3654, 11.9609) -> (10.3311, 12.1076) centre (10.2486, 12.0109) ccw
  arc A229 (10.3311, 12.1076) -> (9.9572, 12.4168) centre (0, 0) ccw
  arc A230 (9.9572, 12.4168) -> (9.8068, 12.423) centre (9.8778, 12.3177) ccw
  line L138 (9.8068, 12.423) -> (9.4387, 12.1747)
  arc A231 (9.1473, 12.1798) -> (9.4387, 12.1747) centre (9.2966, 12.3853) ccw
  line L139 (9.1473, 12.1798) -> (8.757, 12.4634)
  arc A232 (8.6621, 12.7389) -> (8.757, 12.4634) centre (8.9063, 12.6689) ccw
  line L140 (8.6621, 12.7389) -> (8.7845, 13.1657)
  arc A233 (8.7845, 13.1657) -> (8.7321, 13.3069) centre (8.6624, 13.2007) ccw
  arc A234 (8.7321, 13.3069) -> (8.3225, 13.5669) centre (0, 0) ccw
  arc A235 (8.3225, 13.5669) -> (8.1724, 13.5542) centre (8.2561, 13.4586) ccw
  line L141 (8.1724, 13.5542) -> (7.8384, 13.2617)
  arc A236 (7.5487, 13.2302) -> (7.8384, 13.2617) centre (7.671, 13.4528) ccw
  line L142 (7.5487, 13.2302) -> (7.1259, 13.4627)
  arc A237 (6.9972, 13.7241) -> (7.1259, 13.4627) centre (7.2482, 13.6853) ccw
  line L143 (6.9972, 13.7241) -> (7.0651, 14.1629)
  arc A238 (7.0651, 14.1629) -> (6.9955, 14.2964) centre (6.9396, 14.1823) ccw
  arc A239 (6.9955, 14.2964) -> (6.5565, 14.503) centre (0, 0) ccw
  arc A240 (6.5565, 14.503) -> (6.4092, 14.4716) centre (6.5042, 14.3872) ccw
  line L144 (6.4092, 14.4716) -> (6.1144, 14.1395)
  arc A241 (5.831, 14.072) -> (6.1144, 14.1395) centre (5.9245, 14.3082) ccw
  line L145 (5.831, 14.072) -> (5.3824, 14.2496)
  arc A242 (5.222, 14.4929) -> (5.3824, 14.2496) centre (5.4759, 14.4858) ccw
  line L146 (5.222, 14.4929) -> (5.2344, 14.9367)
  arc A243 (5.2344, 14.9367) -> (5.1485, 15.0604) centre (5.1074, 14.9403) ccw
  arc A244 (5.1485, 15.0604) -> (4.6871, 15.2104) centre (0, 0) ccw
  arc A245 (4.6871, 15.2104) -> (4.5449, 15.1607) centre (4.6497, 15.089) ccw
  line L147 (4.5449, 15.1607) -> (4.294, 14.7944)
  arc A246 (4.0213, 14.6919) -> (4.294, 14.7944) centre (4.0845, 14.9379) ccw
  line L148 (4.0213, 14.6919) -> (3.554, 14.8118)
  arc A247 (3.3643, 15.0331) -> (3.554, 14.8118) centre (3.6171, 15.0579) ccw
  line L149 (3.3643, 15.0331) -> (3.321, 15.475)
  arc A248 (3.321, 15.475) -> (3.2203, 15.587) centre (3.1946, 15.4626) ccw
  arc A249 (3.2203, 15.587) -> (2.7438, 15.6779) centre (0, 0) ccw
  circle A250 centre (0, 0) radius 18
  point P0 (0, 0)
  point P1 (4.6871, 15.2104)
  point P2 (5.1485, 15.0604)
  point P3 (6.5565, 14.503)
  point P4 (8.3225, 13.5669)
  point P5 (9.9572, 12.4168)
  point P6 (11.2865, 11.0959)
  point P7 (11.435, 11.0709)
  point P8 (11.7671, 10.7173)
  point P9 (11.558, 10.1845)
  point P10 (12.7324, 9.5504)
  point P11 (13.0175, 9.1579)
  point P12 (13.8289, 7.8793)
  point P13 (13.7277, 6.9902)
  point P14 (13.8835, 6.2665)
  point P15 (14.5786, 6.1619)
  point P16 (14.7074, 6.084)
  point P17 (14.886, 5.6329)
  point P18 (14.4956, 5.2145)
  point P19 (15.354, 4.1927)
  point P20 (15.7584, 2.2353)
  point P21 (15.337, 1.4458)
  point P22 (15.2154, 0.7155)
  point P23 (15.8232, 0.3625)
  point P24 (15.9143, 0.2426)
  point P25 (15.1851, -1.1971)
  point P26 (15.7438, -1.6236)
  point P27 (15.8192, -1.7539)
  point P28 (15.7584, -2.2353)
  point P29 (15.4162, -3.584)
  point P30 (15.4746, -3.7228)
  point P31 (15.354, -4.1927)
  point P32 (14.7922, -4.3016)
  point P33 (14.886, -5.6329)
  point P34 (13.6781, -6.7031)
  point P35 (14.0406, -7.3052)
  point P36 (14.0627, -7.4542)
  point P37 (13.2577, -7.8452)
  point P38 (13.0143, -9.0074)
  point P39 (13.0175, -9.1579)
  point P40 (11.7671, -10.7173)
  point P41 (11.435, -11.0709)
  point P42 (8.757, -12.4634)
  point P43 (8.7321, -13.3069)
  point P44 (8.3225, -13.5669)
  point P45 (6.9955, -14.2964)
  point P46 (5.1485, -15.0604)
  point P47 (4.294, -14.7944)
  point P48 (3.554, -14.8118)
  point P49 (3.321, -15.475)
  point P50 (3.2203, -15.587)
  point P51 (2.7438, -15.6779)
  point P52 (1.2414, -15.8677)
  point P53 (0.7572, -15.8981)
  point P54 (0.4799, -15.3975)
  point P55 (-0.6318, -15.8147)
  point P56 (-0.7572, -15.8981)
  point P57 (-1.2414, -15.8677)
  point P58 (-1.4537, -15.3362)
  point P59 (-2.6089, -15.6108)
  point P60 (-2.7438, -15.6779)
  point P61 (-3.2203, -15.587)
  point P62 (-3.3643, -15.0331)
  point P63 (-4.6871, -15.2104)
  point P64 (-5.1485, -15.0604)
  point P65 (-5.222, -14.4929)
  point P66 (-5.831, -14.072)
  point P67 (-6.5565, -14.503)
  point P68 (-6.9955, -14.2964)
  point P69 (-8.3225, -13.5669)
  point P70 (-9.9572, -12.4168)
  point P71 (-10.3311, -12.1076)
  point P72 (-10.6017, -10.9373)
  point P73 (-11.435, -11.0709)
  point P74 (-12.5882, -9.5939)
  point P75 (-13.8289, -7.8793)
  point P76 (-14.0627, -7.4542)
  point P77 (-13.7277, -6.9902)
  point P78 (-14.5786, -6.1619)
  point P79 (-14.7074, -6.084)
  point P80 (-14.886, -5.6329)
  point P81 (-14.4956, -5.2145)
  point P82 (-15.354, -4.1927)
  point P83 (-15.0348, -3.3566)
  point P84 (-15.7584, -2.2353)
  point P85 (-15.8192, -1.7539)
  point P86 (-15.337, -1.4458)
  point P87 (-15.2154, -0.7155)
  point P88 (-15.8232, -0.3625)
  point P89 (-15.9143, -0.2426)
  point P90 (-15.3972, 0.4878)
  point P91 (-15.7438, 1.6236)
  point P92 (-15.8192, 1.7539)
  point P93 (-15.7584, 2.2353)
  point P94 (-15.2147, 2.4138)
  point P95 (-15.4162, 3.584)
  point P96 (-15.4746, 3.7228)
  point P97 (-14.4104, 4.9359)
  point P98 (-14.886, 5.6329)
  point P99 (-14.7074, 6.084)
  point P100 (-14.0627, 7.4542)
  point P101 (-13.0143, 9.0074)
  point P102 (-13.0175, 9.1579)
  point P103 (-12.7324, 9.5504)
  point P104 (-11.7671, 10.7173)
  point P105 (-10.3311, 12.1076)
  point P106 (-8.7321, 13.3069)
  point P107 (-8.3225, 13.5669)
  point P108 (-7.0651, 14.1629)
  point P109 (-6.9955, 14.2964)
  point P110 (-6.5565, 14.503)
  point P111 (-5.1485, 15.0604)
  point P112 (-4.6871, 15.2104)
  point P113 (-4.294, 14.7944)
  point P114 (-3.2203, 15.587)
  point P115 (-1.6695, 15.1405)
  point P116 (-1.3553, 15.7692)
  point P117 (-1.2414, 15.8677)
  point P118 (-0.4799, 15.3975)
  point P119 (0.6318, 15.8147)
  point P120 (0.7572, 15.8981)
  point P121 (1.2414, 15.8677)
  point P122 (1.4537, 15.3362)
  point P123 (2.6089, 15.6108)
  dimension "d0" = 36
  constraints: 500 point on circle, 300 end point, 251 centre point, 1 coincident
  measures "d0" diameter of A250
extrude "押し出し1" add sketch "スケッチ1" along normal mid plane 7
